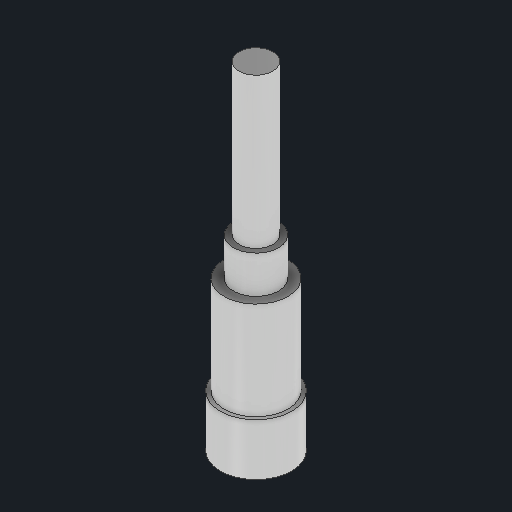
# Autodesk Inventor part: gx16_4pin_cable_plug
Saved by Autodesk Inventor 2027.1 (Build 311270010, 270A)
## iProperties
Created: 2026-11-03
Part Number: gx16_4pin_cable_plug
Material: Generic
Document SubType Name: Modeling
Designer: alexg
Density: 1 g/cm^3
Appearance: Chrome - Polished
Author: alexg
Autodesk Inventor part; units mm, degrees
ref_plane "Work Plane1" through (0, 2.2, 0) normal (0, 1, 0) x (-1, 0, 0)
sketch "Knurled coupling nut sketch" plane through (0, 2.2, 0) normal (0, 1, 0) x (-1, 0, 0)
  circle A0 centre (0, 0) radius 9.5
  circle A1 centre (0, 0) radius 8.05
  constraints: 2 centre point
extrude "Knurled coupling nut" add sketch "Knurled coupling nut sketch" along normal blind 9.8
ref_plane "Work Plane2" through (0, 12, 0) normal (0, 1, 0) x (-1, 0, 0)
sketch "Nut end sketch" plane through (0, 12, 0) normal (0, 1, 0) x (-1, 0, 0)
  circle A0 centre (0, 0) radius 9.5
  constraints: 1 centre point
extrude "Nut end" add sketch "Nut end sketch" along normal blind 4
ref_plane "Work Plane3" through (0, 16, 0) normal (0, 1, 0) x (-1, 0, 0)
sketch "Body sketch" plane through (0, 16, 0) normal (0, 1, 0) x (-1, 0, 0)
  circle A0 centre (0, 0) radius 8.5
  constraints: 1 centre point
extrude "Body" add sketch "Body sketch" along normal blind 26
ref_plane "Work Plane4" through (0, 42, 0) normal (0, 1, 0) x (-1, 0, 0)
sketch "Cable clamp sketch" plane through (0, 42, 0) normal (0, 1, 0) x (-1, 0, 0)
  circle A0 centre (0, 0) radius 6
  constraints: 1 centre point
extrude "Cable clamp" add sketch "Cable clamp sketch" along normal blind 10
ref_plane "Work Plane5" through (0, 52, 0) normal (0, 1, 0) x (-1, 0, 0)
sketch "Cable sketch" plane through (0, 52, 0) normal (0, 1, 0) x (-1, 0, 0)
  circle A0 centre (0, 0) radius 4.5
  constraints: 1 centre point
extrude "Cable" add sketch "Cable sketch" along normal blind 40
body "Solid1"
